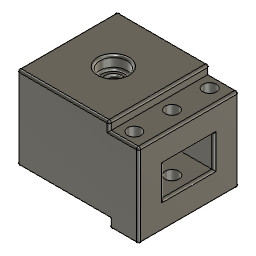
Bracket (Autodesk Fusion 360 design; units mm, degrees)
Autodesk Fusion 360 part; units mm, degrees
sketch "Sketch1" plane through (0, 0, 0) normal (0, 0, 1) x (1, 0, 0)
  line L0 (-14.5, 12) -> (14.5, 12)
  line L1 (14.5, 12) -> (14.5, -12)
  line L2 (14.5, -12) -> (-14.5, -12)
  line L3 (-14.5, -12) -> (-14.5, 12)
  line L4 (7.5, 12) -> (7.5, -12)
  circle A0 centre (10.5, 9) radius 1.65
  circle A1 centre (10.5, 0) radius 1.65
  circle A2 centre (10.5, -9) radius 1.65
  dimension "d1" = 29
  dimension "d2" = 24
  dimension "d3" = 14.5
  dimension "d4" = 12
  dimension "d5" = 22
  dimension "d6" = 3.3
  dimension "d7" = 3
  dimension "d8" = 3
  dimension "d11" = 0
  dimension "d12" = -9
  constraint horizontal L0
  constraint vertical L1
  constraint horizontal L2
  constraint vertical L3
  constraint coincident L0 L4.start
  constraint coincident L2 L4.end
  constraint perpendicular L2 L4
  measures "d1" distance of L0.start L0.end
  measures "d2" distance of L0.start L2.end
  measures "d3" distance of origin L3
  measures "d4" distance of origin L0
  measures "d5" distance of L3 L4
  measures "d6" diameter of A0
  measures "d7" distance of L0 A0.centre
  measures "d8" distance of L4 A0.centre
extrude "Extrude1" add sketch "Sketch1" along normal blind 6.5 contours L0 L2 L3 L4 makes body 1
extrude "Extrude2" add sketch "Sketch1" along normal blind 4.5 contours L0 L1 L2 L4 bodies 1
extrude "Extrude3" add sketch "Sketch1" along normal blind 10.5 contours A0 | A1 | A2 bodies 1
extrude "Extrude4" add sketch "Sketch1" along normal blind 4.5 from surface at 6.5 separate body makes body 2
sketch "Sketch2" plane through (0, 0, 6.5) normal (0, 0, -1) x (1, 0, 0)
  circle A0 centre (10.5, 9) radius 1.65
  circle A1 centre (10.5, 0) radius 1.65
  circle A2 centre (10.5, -9) radius 1.65
  line L0 (14.5, 12) -> (-14.5, 12)
  line L1 (-14.5, 12) -> (-14.5, -12)
  line L2 (-14.5, -12) -> (14.5, -12)
  line L3 (14.5, -12) -> (14.5, 12)
  line L4 (7.5, 12) -> (7.5, -12)
  dimension "d22" = 7
  constraint coincident L0 L4.start
  constraint coincident L2 L4.end
  constraint vertical L4
  measures "d22" distance of L3 L4
extrude "Extrude5" add sketch "Sketch2" along normal blind 2 separate body contours L0 L2 L3 L4 makes body 3
combine "Combine1" operation add target body 2 tool bodies 3
sketch "Sketch4" plane through (0, 0, 11) normal (0, 0, 1) x (-1, 0, 0)
  circle A0 centre (-10.5, 9) radius 1.65
  circle A1 centre (-10.5, 0) radius 1.65
  circle A2 centre (-10.5, -9) radius 1.65
  line L0 (14.5, 12) -> (-14.5, 12)
  line L1 (-14.5, 12) -> (-14.5, -12)
  line L2 (-14.5, -12) -> (14.5, -12)
  line L3 (14.5, -12) -> (14.5, 12)
  line L4 (-14.5, 12) -> (14.5, 12)
  line L5 (14.5, 12) -> (14.5, -12)
  line L6 (14.5, -12) -> (-14.5, -12)
  line L7 (-14.5, -12) -> (-14.5, 12)
  line L8 (14.5, 6) -> (-14.5, 6)
  line L9 (14.5, -6) -> (-14.5, -6)
  dimension "d28" = 6
  dimension "d48" = 12
  constraint horizontal L4
  constraint vertical L5
  constraint horizontal L6
  constraint vertical L7
  constraint coincident L2.end L3.start
  constraint coincident L0.end L1.start
  constraint coincident L3 L8.start
  constraint perpendicular L1 L8
  constraint coincident L7 L8.end
  constraint coincident L5 L9.start
  constraint coincident L7 L9.end
  constraint perpendicular L7 L9
  measures "d28" distance of L4 L8
  measures "d48" distance of L8 L9
extrude "Extrude7" add sketch "Sketch4" along normal blind 7 contours A0 | L0 L1 L3 L4 L5 L7 L8 bodies 2
copy_body "CopyPasteBodies1" bodies 1 makes body 4
move_body "Move1" bodies 4 to x (1, 0, 0) y (0, 1, 0) z (0, 0, 1) at (0, 0, 20)
extrude "Extrude8" add 1 faces at (-4.8333, 4, 20) along direction (0, 0, -1) up to surface (2 mm away) on bodies 4 bodies 4 2
extrude "Extrude9" cut 3 faces at (10.897, -8.7079, 30.5) (10.9032, 0.3741, 30.5) (10.9955, 9.2386, 30.5) along direction (0, 0, -1) blind 11 on bodies 4 bodies 4
sketch "Sketch5" plane through (0, 0, 26.5) normal (0, 0, 1) x (-1, 0, 0)
  line L0 (-7.5, -12) -> (14.5, -12)
  line L1 (14.5, -12) -> (14.5, 12)
  line L2 (14.5, 12) -> (-7.5, 12)
  line L3 (-7.5, 12) -> (-7.5, -12)
  line L4 (11.124, 6) -> (-21.0805, 6) construction
  circle A0 centre (3.5, 0) radius 1.65
  circle A1 centre (3.5, 0) radius 3.25
  line L5 (-14.5, 12) -> (-14.5, -12)
  line L6 (14.5, -12) -> (-14.5, -12)
  line L7 (-14.5, -12) -> (-14.5, 12)
  line L8 (-14.5, 12) -> (14.5, 12)
  line L9 (14.5, 12) -> (14.5, -12)
  line L10 (14.5, -6) -> (-14.5, -6)
  line L11 (-7.5, 12) -> (-7.5, -12)
  circle A2 centre (-10.5, 9) radius 1.6
  circle A3 centre (-10.5, 0) radius 1.6
  circle A4 centre (-10.5, -9) radius 1.6
  dimension "d39" = 3.3
  dimension "d40" = 6
  dimension "d41" = 11
  dimension "d44" = 6.5
  dimension "d47" = 18
  dimension "d51" = 29
  dimension "d52" = 6
  dimension "d53" = 6
  dimension "d54" = 7
  dimension "d55" = 3.2
  dimension "d56" = 3
  dimension "d57" = 3
  dimension "d58" = 24
  dimension "d61" = 0
  dimension "d62" = -18
  constraint horizontal L4
  constraint concentric A0 A1
  constraint horizontal L6
  constraint vertical L7
  constraint horizontal L8
  constraint vertical L9
  constraint coincident L0.end L1.start
  constraint coincident L9 L10.start
  constraint coincident L7 L10.end
  constraint perpendicular L7 L10
  constraint coincident L8 L2.end
  constraint coincident L6 L0.start
  constraint perpendicular L6 L11
  measures "d39" diameter of A0
  measures "d40" distance of L4 A0.centre
  measures "d41" distance of L1 A0.centre
  measures "d44" diameter of A1
  measures "d47" distance of A0.centre L5
  measures "d51" distance of L0.end L5.end
  measures "d52" distance of L6 L10
  measures "d53" distance of A0.centre L10
  measures "d54" distance of L7 L11
  measures "d55" diameter of A2
  measures "d56" distance of L11 A2.centre
  measures "d57" distance of L8 A2.centre
  measures "d58" distance of L6 L8
extrude "Extrude10" cut sketch "Sketch5" against normal blind 11.358 contours A0 bodies 4
delete_body "RemoveBody1" bodies 1
extrude "Extrude11" add sketch "Sketch5" against normal blind 4 contours A1 bodies 4
extrude "Extrude12" add sketch "Sketch4" along normal blind 7 contours L1 L2 L3 L5 L6 L7 L9 bodies 4
delete_face "DeleteFace1" 1 faces at (12.1418, 8.8357, 11.1667) on bodies 4
delete_face "DeleteFace2" 1 faces at (12.1418, 0.1643, 6.6667) on bodies 4
delete_face "DeleteFace3" 1 faces at (12.1418, -9.1643, 6.6667) on bodies 4
delete_face "DeleteFace4" 1 faces at (12.1418, -9.1643, 22.8333) on bodies 4
delete_face "DeleteFace5" 1 faces at (12.1479, 0.0822, 22.8333) on bodies 4
delete_face "DeleteFace6" 1 faces at (12.1479, 9.0822, 22.8333) on bodies 4
extrude "Extrude13" cut sketch "Sketch1" along normal blind 11 contours A0 | A1 | A2 bodies 4
extrude "Extrude14" cut sketch "Sketch5" against normal blind 7 contours A2 | A3 | A4 bodies 4
extrude "Extrude15" cut sketch "Sketch5" against normal blind 3 contours A1 bodies 4
fillet "Fillet5" radius 0.5 7 edges at (-3.5, -12, 26.5) (-14.5, 0, 26.5) (-3.5, 12, 26.5) (7.5, 0, 26.5) (14.5, -12, 14.5) (14.5, 12, 14.5) (14.5, 0, 4.5) on bodies 4
fillet "Fillet6" radius 0.5 12 edges at (-14.5, 12, 16.25) (-14.3536, 11.8536, 26.3536) (-14.5, 0, 6.5) (-14.5, -12, 16.25) (-14.3536, -11.8536, 26.3536) (10.75, 12, 4.5) (14.3536, 11.8536, 4.6464) (7.5, 0, 4.5) (14.3536, -11.8536, 4.6464) (10.75, -12, 4.5) (-3.5, 12, 6.5) (-3.5, -12, 6.5) on bodies 4
fillet "Fillet7" radius 0.5 4 edges at (7.5, -12, 6) (7.6464, -11.8536, 4.6464) (7.5, 12, 6) (7.6464, 11.8536, 4.6464) on bodies 4
fillet "Fillet8" radius 0.5 9 edges at (10.75, -12, 24.5) (14.3536, -11.8536, 24.5) (14.5, 0, 24.5) (14.3536, 11.8536, 24.5) (10.75, 12, 24.5) (7.5, -12, 25.25) (7.3536, -11.8536, 26.3536) (7.5, 12, 25.25) (7.3536, 11.8536, 26.3536) on bodies 4
fillet "Fillet9" radius 0.5 8 edges at (14.5, -6, 14.5) (14.5, 0, 18) (14.5, 6, 14.5) (14.5, 0, 11) (-14.5, 6, 14.5) (-14.5, 0, 18) (-14.5, -6, 14.5) (-14.5, 0, 11) on bodies 4
fillet "Fillet10" radius 0.5 3 edges at (-0.4699, -1.1753, 26.5) (-0.4699, -1.1753, 23.5) (-1.9617, 0.5967, 23.5) on bodies 4
move_face "OffsetFaces1" offset -0.3 1 faces at (8.7167, 0, 18) on bodies 4
equation "d3 = d1 / 2"
equation "d4 = d2 / 2"
